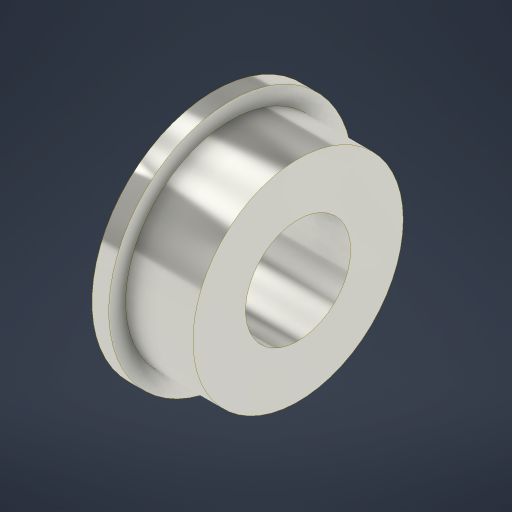
# Autodesk Inventor part: MF105ZZ
Saved by Autodesk Inventor 2023 (Build 270158000, 158)
## iProperties
Created: 2026-11-12
Part Number: MF105ZZ
Material: Steel
Document SubType Name: Modeling
Designer: szykr
Density: 7.85 g/cm^3
Appearance: Silver
Author: szykr
Autodesk Inventor part; units mm, degrees
ref_plane "YZ Plane" through (0, 0, 0) normal (1, 0, 0) x (0, 1, 0)
ref_plane "XZ Plane" through (0, 0, 0) normal (0, 1, 0) x (-1, 0, 0)
ref_plane "XY Plane" through (0, 0, 0) normal (0, 0, 1) x (1, 0, 0)
sketch "Sketch1" plane through (0, 0, 0) normal (0, 1, 0) x (-1, 0, 0)
  line L0 (0, 0) -> (-10.1661, 0)
  line L1 (0, -5.8) -> (-0.8, -5.8)
  line L2 (-0.8, -5.8) -> (-0.8, -5)
  line L3 (-0.8, -5) -> (-4, -5)
  line L4 (-4, -5) -> (-4, -2.5)
  line L5 (-4, -2.5) -> (0, -2.5)
  line L6 (0, -2.5) -> (0, -5.8)
  dimension "d0" = 11.6
  dimension "d1" = 0.8
  dimension "d2" = 10
  dimension "d3" = 5
  dimension "d4" = 4
  constraints: 14 end point, 4 perpendicular, 1 horizontal, 1 vertical alignment
  measures "d0" diameter of L1 L0
  measures "d1" distance between parallel lines of L6 L2
  measures "d2" diameter of L3 L0
  measures "d3" diameter of L5 L0
  measures "d4" distance between parallel lines of L6 L4
revolve "Revolution1" add sketch "Sketch1" angle 360 about axis through (0, 0, 0) along (1, 0, 0)
body "Solid1"
